350002_P01_FRONT-DECOR-BLOCK-ASSY-DT_CAD (Autodesk Fusion 360 design; units mm, degrees)
part number: 2026-11-01-00-32-53-653
description: FRONT - DECOR SKIN - DT | Tấm ốp alu khối trên | P01
part number: 351201
description: FRONT - DECOR BACK PLATE - DT | Tấm hậu khối trên | P01
part number: 351202
description: FRONT - DOOR CATCH - IN DT | Nam châm hít cửa | P01
part number: 368007
description: FRONT - FRAME-STOP SEAL | Gioăng chặn cửa trên | P01
part number: 368005
description: FRONT - DOOR TOP STOP - DT | Nẹp chặn cửa trên | P01
part number: 351203
description: FRONT - DECOR FRAME - DT | Khung trang trí trên (hàn) | P01
part number: 351204
description: FRONT - DECOR FRAME DT - BACK RING BOTTOM | Mặt trước - khung khối trên - vòng sau - thanh dưới | P01
part number: 352201
description: FRONT - DECOR FRAME DT - BACK RING DR JOINT | Mặt trước - khung khối trên - vòng sau - thanh nối khối phải | P01
part number: 352202
description: FRONT - DECOR FRAME DT - BACK RING TOP | Mặt trước - khung khối trên - vòng sau - thanh trên | P01
part number: 352203
description: FRONT - DECOR FRAME DT - BACK RING SLOPE OVER DL | Mặt trước - khung khối trên - vòng sau - thanh dốc trên khối trái | P01
part number: 352204
description: FRONT - DECOR FRAME DT - BACK RING POST | Mặt trước - khung khối trên - vòng sau - thanh đứng | P01
part number: 352205
description: FRONT - DECOR FRAME DT - FRONT FACET TUBE | Mặt trước - khung khối trên - thanh mặt vát trước | P01
part number: 352206
description: FRONT - DECOR FRAME DT - CATCH AND STOP RAIL | Mặt trước - khung khối trên - thanh gắn chốt hít và nẹp chặn | P01
part number: 352207
description: FRONT - DECOR FRAME DT - CHAMFER TUBE ALONG X | Mặt trước - khung khối trên - thanh vát dọc trục X | P01
part number: 352208
description: FRONT - DECOR FRAME DT - UNDERSIDE CROSS TUBE LEFT | Mặt trước - khung khối trên - thanh ngang mặt dưới - trái | P01
part number: 352209
description: FRONT - DECOR FRAME DT - UNDERSIDE CROSS TUBE OVER THE CATCH | Mặt trước - khung khối trên - thanh ngang mặt dưới - trên chốt hít | P01
part number: 352210
description: FRONT - DECOR FRAME DT - CHAMFER CROSS TUBE - 3 OFF | Mặt trước - khung khối trên - thanh ngang vát (3 thanh) | P01
part number: 352211
Autodesk Fusion 360 part; units mm, degrees
(part 1 of 2)
sketch "PLAN - DT FACETS (SKELETON)" plane through (0, 0, 0) normal (0, 0, 1) x (1, 0, 0) in component "351201 FRONT - DECOR SKIN - DT"
  line L0 (-1250, -647.26) -> (-1250, -670)
  line L1 (-1250, -670) -> (-1154, -753)
  line L2 (-1154, -753) -> (-969, -767)
  line L3 (-969, -767) -> (230, -850)
  line L4 (230, -850) -> (449, -672)
  line L5 (449, -672) -> (449, -647.26)
  line L6 (449, -647.26) -> (-1250, -647.26)
  point P0 (-5000, -5000)
  dimension "d2514" = 5000
  dimension "d2515" = 5000
  dimension "d2516" = 3750
  dimension "d2517" = 3846
  dimension "d2518" = 4031
  dimension "d2519" = 5230
  dimension "d2520" = 5449
  dimension "d2521" = 4330
  dimension "d2522" = 4247
  dimension "d2523" = 4233
  dimension "d2524" = 4150
  dimension "d2526" = 4352.74
  constraint vertical L0
  constraint vertical L5
  constraint horizontal L6
  measures "d2514" horizontal distance of origin P0
  measures "d2515" vertical distance of origin P0
  measures "d2516" horizontal distance of L0.start P0
  measures "d2517" horizontal distance of L1.end P0
  measures "d2518" horizontal distance of L2.end P0
  measures "d2519" horizontal distance of L3.end P0
  measures "d2520" horizontal distance of L4.end P0
  measures "d2521" vertical distance of L0.end P0
  measures "d2522" vertical distance of L1.end P0
  measures "d2523" vertical distance of L2.end P0
  measures "d2524" vertical distance of L3.end P0
  measures "d2526" vertical distance of L5.end P0
extrude "EXTRUDE - DT OUTER SHAPE" add sketch "PLAN - DT FACETS (SKELETON)" along normal blind 280 from surface at 2120 makes body 1 in component "351201 FRONT - DECOR SKIN - DT"
sketch "SLOPE - DT BOTTOM OVER DL" plane through (0, 0, 0) normal (0, 1, 0) x (1, 0, 0) in component "351201 FRONT - DECOR SKIN - DT"
  line L0 (-1250, -2120) -> (-972, -2120)
  line L1 (-972, -2120) -> (-1250, -2397)
  line L2 (-1250, -2397) -> (-1250, -2120)
  point P0 (-5000, 5000)
  dimension "d2530" = 5000
  dimension "d2531" = 5000
  dimension "d2532" = 4028
  dimension "d2533" = 3750
  constraint vertical L2
  constraint horizontal L0
  measures "d2530" horizontal distance of origin P0
  measures "d2531" vertical distance of origin P0
  measures "d2532" horizontal distance of L0.end P0
  measures "d2533" horizontal distance of L1.end P0
extrude "CUT - DT BOTTOM SLOPE" cut sketch "SLOPE - DT BOTTOM OVER DL" along normal blind 205 from surface at -850 bodies 1 in component "351201 FRONT - DECOR SKIN - DT"
sketch "CHAMFER - DT TOP FRONT" plane through (0, 0, 0) normal (1, 0, 0) x (0, 0, -1) in component "351201 FRONT - DECOR SKIN - DT"
  line L0 (-2200, -850) -> (-2400, -672)
  line L1 (-2400, -672) -> (-2400, -850)
  line L2 (-2400, -850) -> (-2200, -850)
  point P0 (5000, -5000)
  dimension "d2539" = 5000
  dimension "d2540" = 5000
  dimension "d2544" = 4150
  constraint vertical L1
  constraint horizontal L2
  measures "d2539" horizontal distance of origin P0
  measures "d2540" vertical distance of origin P0
  measures "d2544" vertical distance of L1.end P0
extrude "CUT - DT TOP CHAMFER" cut sketch "CHAMFER - DT TOP FRONT" along normal blind 2500 from surface at -1250 bodies 1 in component "351201 FRONT - DECOR SKIN - DT"
shell "SHELL - DT SKIN 3 MM (OPEN AT THE BACK AND AT DL, DR)" thickness 3 removed faces 4 at (449, -663.7533, 2213.3333) at (376, -731.3333, 2240) at (-591, -647.26, 2306.6667) at (-1125.3333, -682.5067, 2272.7818) on bodies 1 in component "351201 FRONT - DECOR SKIN - DT"
sketch "SLOT - FIXED GLASS TOP CHANNEL" plane through (0, 0, 0) normal (0, 0, 1) x (1, 0, 0) in component "351201 FRONT - DECOR SKIN - DT"
  line L0 (-65.0827, -707.5) -> (249.8472, -707.5)
  line L1 (249.8472, -707.5) -> (249.8472, -690.5)
  line L2 (249.8472, -690.5) -> (-65.0827, -690.5)
  line L3 (-65.0827, -690.5) -> (-65.0827, -707.5)
  point P0 (-5000, -5000)
  dimension "d2549" = 5000
  dimension "d2550" = 5000
  dimension "d2552" = 4934.9173
  dimension "d2553" = 4292.5
  dimension "d2554" = 4309.5
  constraint vertical L1
  constraint vertical L3
  constraint horizontal L0
  constraint horizontal L2
  measures "d2549" horizontal distance of origin P0
  measures "d2550" vertical distance of origin P0
  measures "d2552" horizontal distance of L2.end P0
  measures "d2553" vertical distance of L0.start P0
  measures "d2554" vertical distance of L1.end P0
extrude "CUT - SKIN SLOT FOR THE TOP CHANNEL" cut sketch "SLOT - FIXED GLASS TOP CHANNEL" along normal blind 5 from surface at 2119 bodies 1 in component "351201 FRONT - DECOR SKIN - DT"
sketch "NOTCH - OVER DR'S LEDGE SPIGOTS" plane through (0, 0, 0) normal (0, 0, 1) x (1, 0, 0) in component "351201 FRONT - DECOR SKIN - DT"
  line L0 (254, -673.88) -> (428.75, -673.88)
  line L1 (428.75, -673.88) -> (428.75, -646.26)
  line L2 (428.75, -646.26) -> (254, -646.26)
  line L3 (254, -646.26) -> (254, -673.88)
  point P0 (-5000, -5000)
  dimension "d2558" = 5000
  dimension "d2559" = 5000
  dimension "d2560" = 5428.75
  dimension "d2561" = 5254
  dimension "d2563" = 4353.74
  constraint vertical L1
  constraint vertical L3
  constraint horizontal L0
  constraint horizontal L2
  measures "d2558" horizontal distance of origin P0
  measures "d2559" vertical distance of origin P0
  measures "d2560" horizontal distance of L0.end P0
  measures "d2561" horizontal distance of L2.end P0
  measures "d2563" vertical distance of L1.end P0
extrude "CUT - UNDERSIDE NOTCH" cut sketch "NOTCH - OVER DR'S LEDGE SPIGOTS" along normal blind 5 from surface at 2119 bodies 1 in component "351201 FRONT - DECOR SKIN - DT"
sketch "OUTLINE - DT BACK PLATE" plane through (0, 0, 0) normal (0, 1, 0) x (1, 0, 0) in component "351202 FRONT - DECOR BACK PLATE - DT"
  line L0 (-970.7605, -2123) -> (449, -2123)
  line L1 (449, -2123) -> (449, -2397)
  line L2 (449, -2397) -> (-1245.7497, -2397)
  line L3 (-1245.7497, -2397) -> (-970.7605, -2123)
  point P0 (-5000, 5000)
  dimension "d2567" = 5000
  dimension "d2568" = 5000
  dimension "d2569" = 4029.2395
  dimension "d2570" = 5449
  dimension "d2571" = 3754.2503
  constraint vertical L1
  constraint horizontal L0
  constraint horizontal L2
  measures "d2567" horizontal distance of origin P0
  measures "d2568" vertical distance of origin P0
  measures "d2569" horizontal distance of L0.start P0
  measures "d2570" horizontal distance of L0.end P0
  measures "d2571" horizontal distance of L2.end P0
extrude "EXTRUDE - DT BACK PLATE" add sketch "OUTLINE - DT BACK PLATE" along normal blind 2 from surface at -649.26 separate body makes body 2 in component "351202 FRONT - DECOR BACK PLATE - DT"
sketch "HOLES - J-FRONT-03 RIVNUTS (4)" plane through (0, 0, 0) normal (0, 1, 0) x (1, 0, 0) in component "351202 FRONT - DECOR BACK PLATE - DT"
  circle A0 centre (-981.74, -2374) radius 4.765
  circle A1 centre (-578.16, -2374) radius 4.765
  circle A2 centre (-174.58, -2374) radius 4.765
  circle A3 centre (229, -2374) radius 4.765
  point P0 (-5000, 5000)
  dimension "d2577" = 5000
  dimension "d2578" = 5000
  dimension "d2579" = 4018.26
  dimension "d2580" = 7374
  dimension "d2581" = 9.53
  dimension "d2582" = 4421.84
  dimension "d2583" = 7374
  dimension "d2584" = 9.53
  dimension "d2585" = 4825.42
  dimension "d2586" = 7374
  dimension "d2587" = 9.53
  dimension "d2588" = 5229
  dimension "d2589" = 7374
  dimension "d2590" = 9.53
  measures "d2577" horizontal distance of origin P0
  measures "d2578" vertical distance of origin P0
  measures "d2579" horizontal distance of P0 A0.centre
  measures "d2580" vertical distance of P0 A0.centre
  measures "d2581" diameter of A0
  measures "d2582" horizontal distance of P0 A1.centre
  measures "d2583" vertical distance of P0 A1.centre
  measures "d2584" diameter of A1
  measures "d2585" horizontal distance of P0 A2.centre
  measures "d2586" vertical distance of P0 A2.centre
  measures "d2587" diameter of A2
  measures "d2588" horizontal distance of P0 A3.centre
  measures "d2589" vertical distance of P0 A3.centre
  measures "d2590" diameter of A3
extrude "CUT - J-FRONT-03 RIVNUT HOLES" cut sketch "HOLES - J-FRONT-03 RIVNUTS (4)" along normal blind 4 from surface at -650.26 bodies 2 in component "351202 FRONT - DECOR BACK PLATE - DT"
sketch "PLAN - CATCH" plane through (0, 0, 0) normal (0, 0, 1) x (1, 0, 0) in component "368007 FRONT - DOOR CATCH - IN DT"
  line L0 (-154.7195, -691.95) -> (-92.7195, -691.95)
  line L1 (-92.7195, -691.95) -> (-92.7195, -671.95)
  line L2 (-92.7195, -671.95) -> (-154.7195, -671.95)
  line L3 (-154.7195, -671.95) -> (-154.7195, -691.95)
  point P0 (-5000, -5000)
  dimension "d2594" = 5000
  dimension "d2595" = 5000
  dimension "d2596" = 4907.2805
  dimension "d2597" = 4845.2805
  dimension "d2598" = 4308.05
  dimension "d2599" = 4328.05
  constraint vertical L1
  constraint vertical L3
  constraint horizontal L0
  constraint horizontal L2
  measures "d2594" horizontal distance of origin P0
  measures "d2595" vertical distance of origin P0
  measures "d2596" horizontal distance of L0.end P0
  measures "d2597" horizontal distance of L2.end P0
  measures "d2598" vertical distance of L0.start P0
  measures "d2599" vertical distance of L1.end P0
extrude "EXTRUDE - CATCH" add sketch "PLAN - CATCH" along normal blind 26 from surface at 2094 separate body makes body 3 in component "368007 FRONT - DOOR CATCH - IN DT"
sketch "PLAN - PS" plane through (0, 0, 0) normal (0, 0, 1) x (1, 0, 0) in component "368005 FRONT - FRAME-STOP SEAL"
  line L0 (-961, -694.62) -> (-164.7195, -694.62)
  line L1 (-164.7195, -694.62) -> (-164.7195, -690.62)
  line L2 (-164.7195, -690.62) -> (-961, -690.62)
  line L3 (-961, -690.62) -> (-961, -694.62)
  point P0 (-5000, -5000)
  dimension "d2603" = 5000
  dimension "d2604" = 5000
  dimension "d2605" = 4835.2805
  dimension "d2606" = 4039
  dimension "d2607" = 4305.38
  dimension "d2608" = 4309.38
  constraint vertical L1
  constraint vertical L3
  constraint horizontal L0
  constraint horizontal L2
  measures "d2603" horizontal distance of origin P0
  measures "d2604" vertical distance of origin P0
  measures "d2605" horizontal distance of L0.end P0
  measures "d2606" horizontal distance of L2.end P0
  measures "d2607" vertical distance of L0.start P0
  measures "d2608" vertical distance of L1.end P0
extrude "EXTRUDE - PS" add sketch "PLAN - PS" along normal blind 15 from surface at 2105 separate body makes body 4 in component "368005 FRONT - FRAME-STOP SEAL"
sketch "SECTION - DOOR TOP STOP (ANGLE)" plane through (0, 0, 0) normal (1, 0, 0) x (0, 0, -1) in component "351203 FRONT - DOOR TOP STOP - DT"
  line L0 (-2100, -690.62) -> (-2100, -688.62)
  line L1 (-2100, -688.62) -> (-2118, -688.62)
  line L2 (-2118, -688.62) -> (-2118, -670.62)
  line L3 (-2118, -670.62) -> (-2120, -670.62)
  line L4 (-2120, -670.62) -> (-2120, -690.62)
  line L5 (-2120, -690.62) -> (-2100, -690.62)
  point P0 (5000, -5000)
  dimension "d2612" = 5000
  dimension "d2613" = 5000
  dimension "d2617" = 4311.38
  dimension "d2618" = 4329.38
  dimension "d2619" = 4309.38
  constraint vertical L0
  constraint vertical L2
  constraint vertical L4
  constraint horizontal L1
  constraint horizontal L3
  constraint horizontal L5
  measures "d2612" horizontal distance of origin P0
  measures "d2613" vertical distance of origin P0
  measures "d2617" vertical distance of L0.end P0
  measures "d2618" vertical distance of L2.end P0
  measures "d2619" vertical distance of L4.end P0
extrude "EXTRUDE - DOOR TOP STOP" add sketch "SECTION - DOOR TOP STOP (ANGLE)" along normal blind 796.2805 from surface at -961 separate body makes body 5 in component "351203 FRONT - DOOR TOP STOP - DT"
sketch "HOLES - TOP STOP SCREWS (5)" plane through (0, 0, 0) normal (0, 0, 1) x (1, 0, 0) in component "351203 FRONT - DOOR TOP STOP - DT"
  circle A0 centre (-911, -679.62) radius 2.15
  circle A1 centre (-736.9299, -679.62) radius 2.15
  circle A2 centre (-562.8598, -679.62) radius 2.15
  circle A3 centre (-388.7897, -679.62) radius 2.15
  circle A4 centre (-214.7195, -679.62) radius 2.15
  point P0 (-5000, -5000)
  dimension "d2623" = 5000
  dimension "d2624" = 5000
  dimension "d2625" = 4089
  dimension "d2626" = 4320.38
  dimension "d2627" = 4.3
  dimension "d2628" = 4263.0701
  dimension "d2629" = 4320.38
  dimension "d2630" = 4.3
  dimension "d2631" = 4437.1402
  dimension "d2632" = 4320.38
  dimension "d2633" = 4.3
  dimension "d2634" = 4611.2103
  dimension "d2635" = 4320.38
  dimension "d2636" = 4.3
  dimension "d2637" = 4785.2805
  dimension "d2638" = 4320.38
  dimension "d2639" = 4.3
  measures "d2623" horizontal distance of origin P0
  measures "d2624" vertical distance of origin P0
  measures "d2625" horizontal distance of P0 A0.centre
  measures "d2626" vertical distance of P0 A0.centre
  measures "d2627" diameter of A0
  measures "d2628" horizontal distance of P0 A1.centre
  measures "d2629" vertical distance of P0 A1.centre
  measures "d2630" diameter of A1
  measures "d2631" horizontal distance of P0 A2.centre
  measures "d2632" vertical distance of P0 A2.centre
  measures "d2633" diameter of A2
  measures "d2634" horizontal distance of P0 A3.centre
  measures "d2635" vertical distance of P0 A3.centre
  measures "d2636" diameter of A3
  measures "d2637" horizontal distance of P0 A4.centre
  measures "d2638" vertical distance of P0 A4.centre
  measures "d2639" diameter of A4
extrude "CUT - TOP STOP SCREW HOLES" cut sketch "HOLES - TOP STOP SCREWS (5)" along normal blind 4 from surface at 2117 bodies 5 in component "351203 FRONT - DOOR TOP STOP - DT"
sketch "TUBE B01 - BACK RING BOTTOM" plane through (0, 0, 0) normal (0, 1, 0) x (1, 0, 0) in component "352201 FRONT - DECOR FRAME DT - BACK RING BOTTOM"
  line L0 (-973.7714, -2126) -> (449, -2126)
  line L1 (449, -2126) -> (429, -2146)
  line L2 (429, -2146) -> (-965.5082, -2146)
  line L3 (-965.5082, -2146) -> (-973.7714, -2126)
  point P0 (-5000, 5000)
  dimension "d2643" = 5000
  dimension "d2644" = 5000
  dimension "d2645" = 4026.2286
  dimension "d2646" = 5449
  dimension "d2647" = 5429
  dimension "d2648" = 4034.4918
  dimension "d2649" = 7126
  constraint horizontal L0
  constraint horizontal L2
  measures "d2643" horizontal distance of origin P0
  measures "d2644" vertical distance of origin P0
  measures "d2645" horizontal distance of L0.start P0
  measures "d2646" horizontal distance of L0.end P0
  measures "d2647" horizontal distance of L1.end P0
  measures "d2648" horizontal distance of L2.end P0
  measures "d2649" vertical distance of L0.start P0
extrude "EXTRUDE - TUBE B01" add sketch "TUBE B01 - BACK RING BOTTOM" along normal blind 20 from surface at -669.26 separate body makes body 6 in component "352201 FRONT - DECOR FRAME DT - BACK RING BOTTOM"
shell "SHELL - TUBE B01 (ENDS OPEN)" thickness 1.5 removed faces 2 at (-968.2626, -662.5933, 2139.3333) at (442.3333, -662.5933, 2132.6667) on bodies 6 in component "352201 FRONT - DECOR FRAME DT - BACK RING BOTTOM"
sketch "TUBE B02 - BACK RING DR JOINT" plane through (0, 0, 0) normal (0, 1, 0) x (1, 0, 0) in component "352202 FRONT - DECOR FRAME DT - BACK RING DR JOINT"
  line L0 (449, -2126) -> (449, -2394)
  line L1 (449, -2394) -> (429, -2354)
  line L2 (429, -2354) -> (429, -2146)
  line L3 (429, -2146) -> (449, -2126)
  point P0 (-5000, 5000)
  dimension "d2655" = 5000
  dimension "d2656" = 5000
  dimension "d2657" = 5449
  dimension "d2658" = 5429
  constraint vertical L0
  constraint vertical L2
  measures "d2655" horizontal distance of origin P0
  measures "d2656" vertical distance of origin P0
  measures "d2657" horizontal distance of L0.start P0
  measures "d2658" horizontal distance of L1.end P0
extrude "EXTRUDE - TUBE B02" add sketch "TUBE B02 - BACK RING DR JOINT" along normal blind 20 from surface at -669.26 separate body makes body 7 in component "352202 FRONT - DECOR FRAME DT - BACK RING DR JOINT"
shell "SHELL - TUBE B02 (ENDS OPEN)" thickness 1.5 removed faces 2 at (435.6667, -655.9267, 2139.3333) at (442.3333, -662.5933, 2380.6667) on bodies 7 in component "352202 FRONT - DECOR FRAME DT - BACK RING DR JOINT"
sketch "TUBE B03 - BACK RING TOP" plane through (0, 0, 0) normal (0, 1, 0) x (1, 0, 0) in component "352203 FRONT - DECOR FRAME DT - BACK RING TOP"
  line L0 (449, -2394) -> (-1242.7389, -2394)
  line L1 (-1242.7389, -2394) -> (-1174.2591, -2354)
  line L2 (-1174.2591, -2354) -> (429, -2354)
  line L3 (429, -2354) -> (449, -2394)
  point P0 (-5000, 5000)
  dimension "d2667" = 5000
  dimension "d2668" = 5000
  dimension "d2669" = 5449
  dimension "d2670" = 3757.2611
  dimension "d2671" = 3825.7409
  dimension "d2672" = 5429
  dimension "d2674" = 7354
  constraint horizontal L0
  constraint horizontal L2
  measures "d2667" horizontal distance of origin P0
  measures "d2668" vertical distance of origin P0
  measures "d2669" horizontal distance of L0.start P0
  measures "d2670" horizontal distance of L0.end P0
  measures "d2671" horizontal distance of L1.end P0
  measures "d2672" horizontal distance of L2.end P0
  measures "d2674" vertical distance of L1.end P0
extrude "EXTRUDE - TUBE B03" add sketch "TUBE B03 - BACK RING TOP" along normal blind 20 from surface at -669.26 separate body makes body 8 in component "352203 FRONT - DECOR FRAME DT - BACK RING TOP"
shell "SHELL - TUBE B03 (ENDS OPEN)" thickness 1.5 removed faces 2 at (435.6667, -655.9267, 2367.3333) at (-1219.9123, -662.5933, 2380.6667) on bodies 8 in component "352203 FRONT - DECOR FRAME DT - BACK RING TOP"
sketch "TUBE B04 - BACK RING SLOPE OVER DL" plane through (0, 0, 0) normal (0, 1, 0) x (1, 0, 0) in component "352204 FRONT - DECOR FRAME DT - BACK RING SLOPE OVER DL"
  line L0 (-1242.7389, -2394) -> (-973.7714, -2126)
  line L1 (-973.7714, -2126) -> (-965.5082, -2146)
  line L2 (-965.5082, -2146) -> (-1174.2591, -2354)
  line L3 (-1174.2591, -2354) -> (-1242.7389, -2394)
  point P0 (-5000, 5000)
  dimension "d2679" = 5000
  dimension "d2680" = 5000
  dimension "d2681" = 3757.2611
  dimension "d2682" = 4026.2286
  dimension "d2683" = 4034.4918
  dimension "d2684" = 3825.7409
  dimension "d2685" = 7394
  dimension "d2686" = 7126
  dimension "d2687" = 7146
  dimension "d2688" = 7354
  measures "d2679" horizontal distance of origin P0
  measures "d2680" vertical distance of origin P0
  measures "d2681" horizontal distance of L0.start P0
  measures "d2682" horizontal distance of L0.end P0
  measures "d2683" horizontal distance of L1.end P0
  measures "d2684" horizontal distance of L2.end P0
  measures "d2685" vertical distance of L0.start P0
  measures "d2686" vertical distance of L0.end P0
  measures "d2687" vertical distance of L1.end P0
  measures "d2688" vertical distance of L2.end P0
extrude "EXTRUDE - TUBE B04" add sketch "TUBE B04 - BACK RING SLOPE OVER DL" along normal blind 20 from surface at -669.26 separate body makes body 9 in component "352204 FRONT - DECOR FRAME DT - BACK RING SLOPE OVER DL"
shell "SHELL - TUBE B04 (ENDS OPEN)" thickness 1.5 removed faces 2 at (-1197.0857, -655.9267, 2367.3333) at (-971.017, -662.5933, 2132.6667) on bodies 9 in component "352204 FRONT - DECOR FRAME DT - BACK RING SLOPE OVER DL"
sketch "TUBE B05 - BACK RING POST" plane through (0, 0, 0) normal (0, 1, 0) x (1, 0, 0) in component "352205 FRONT - DECOR FRAME DT - BACK RING POST"
  line L0 (-271.5, -2146) -> (-251.5, -2146)
  line L1 (-251.5, -2146) -> (-251.5, -2354)
  line L2 (-251.5, -2354) -> (-271.5, -2354)
  line L3 (-271.5, -2354) -> (-271.5, -2146)
  point P0 (-5000, 5000)
  dimension "d2693" = 5000
  dimension "d2694" = 5000
  dimension "d2695" = 4748.5
  dimension "d2696" = 4728.5
  constraint vertical L1
  constraint vertical L3
  constraint horizontal L0
  constraint horizontal L2
  measures "d2693" horizontal distance of origin P0
  measures "d2694" vertical distance of origin P0
  measures "d2695" horizontal distance of L0.end P0
  measures "d2696" horizontal distance of L2.end P0
extrude "EXTRUDE - TUBE B05" add sketch "TUBE B05 - BACK RING POST" along normal blind 20 from surface at -669.26 separate body makes body 10 in component "352205 FRONT - DECOR FRAME DT - BACK RING POST"
shell "SHELL - TUBE B05 (ENDS OPEN)" thickness 1.5 removed faces 2 at (-264.8333, -662.5933, 2146) at (-258.1667, -662.5933, 2354) on bodies 10 in component "352205 FRONT - DECOR FRAME DT - BACK RING POST"
sketch "TUBE F01 - FRONT FACET TUBE" plane through (0, 0, 0) normal (0, 0, 1) x (1, 0, 0) in component "352206 FRONT - DECOR FRAME DT - FRONT FACET TUBE"
  line L0 (-969, -760.9856) -> (236.8189, -844.4577)
  line L1 (236.8189, -844.4577) -> (259.5487, -825.9833)
  line L2 (259.5487, -825.9833) -> (-969, -740.9378)
  line L3 (-969, -740.9378) -> (-969, -760.9856)
  point P0 (-5000, -5000)
  dimension "d2703" = 5000
  dimension "d2704" = 5000
  dimension "d2705" = 5236.8189
  dimension "d2706" = 5259.5487
  dimension "d2707" = 4031
  dimension "d2708" = 4239.0144
  dimension "d2709" = 4155.5423
  dimension "d2710" = 4174.0167
  dimension "d2711" = 4259.0622
  constraint vertical L3
  measures "d2703" horizontal distance of origin P0
  measures "d2704" vertical distance of origin P0
  measures "d2705" horizontal distance of L0.end P0
  measures "d2706" horizontal distance of L1.end P0
  measures "d2707" horizontal distance of L2.end P0
  measures "d2708" vertical distance of L0.start P0
  measures "d2709" vertical distance of L0.end P0
  measures "d2710" vertical distance of L1.end P0
  measures "d2711" vertical distance of L2.end P0
extrude "EXTRUDE - TUBE F01" add sketch "TUBE F01 - FRONT FACET TUBE" along normal blind 20 from surface at 2126 separate body makes body 11 in component "352206 FRONT - DECOR FRAME DT - FRONT FACET TUBE"
shell "SHELL - TUBE F01 (ENDS OPEN)" thickness 1.5 removed faces 2 at (244.3955, -838.2995, 2139.3333) at (-969, -747.6204, 2132.6667) on bodies 11 in component "352206 FRONT - DECOR FRAME DT - FRONT FACET TUBE"
sketch "TUBE F02 - CATCH AND STOP RAIL" plane through (0, 0, 0) normal (0, 0, 1) x (1, 0, 0) in component "352207 FRONT - DECOR FRAME DT - CATCH AND STOP RAIL"
  line L0 (-973.7714, -689.26) -> (427.7644, -689.26)
  line L1 (427.7644, -689.26) -> (449, -672)
  line L2 (449, -672) -> (449, -669.26)
  line L3 (449, -669.26) -> (-973.7714, -669.26)
  line L4 (-973.7714, -669.26) -> (-973.7714, -689.26)
  point P0 (-5000, -5000)
  dimension "d2716" = 5000
  dimension "d2717" = 5000
  dimension "d2718" = 5427.7644
  dimension "d2719" = 5449
  dimension "d2720" = 4026.2286
  dimension "d2721" = 4310.74
  dimension "d2722" = 4328
  dimension "d2723" = 4330.74
  constraint vertical L2
  constraint vertical L4
  constraint horizontal L0
  constraint horizontal L3
  measures "d2716" horizontal distance of origin P0
  measures "d2717" vertical distance of origin P0
  measures "d2718" horizontal distance of L0.end P0
  measures "d2719" horizontal distance of L1.end P0
  measures "d2720" horizontal distance of L3.end P0
  measures "d2721" vertical distance of L0.start P0
  measures "d2722" vertical distance of L1.end P0
  measures "d2723" vertical distance of L2.end P0
extrude "EXTRUDE - TUBE F02" add sketch "TUBE F02 - CATCH AND STOP RAIL" along normal blind 20 from surface at 2126 separate body makes body 12 in component "352207 FRONT - DECOR FRAME DT - CATCH AND STOP RAIL"
shell "SHELL - TUBE F02 (ENDS OPEN)" thickness 1.5 removed faces 3 at (449, -671.0867, 2132.6667) at (434.8429, -683.5067, 2132.6667) at (-973.7714, -675.9267, 2132.6667) on bodies 12 in component "352207 FRONT - DECOR FRAME DT - CATCH AND STOP RAIL"
sketch "TUBE F03 - CHAMFER TUBE ALONG X" plane through (0, 0, 0) normal (1, 0, 0) x (0, 0, -1) in component "352208 FRONT - DECOR FRAME DT - CHAMFER TUBE ALONG X"
  line L0 (-2290.9912, -760.9856) -> (-2305.9312, -747.6891)
  line L1 (-2305.9312, -747.6891) -> (-2292.6346, -732.7492)
  line L2 (-2292.6346, -732.7492) -> (-2277.6947, -746.0457)
  line L3 (-2277.6947, -746.0457) -> (-2290.9912, -760.9856)
  point P0 (5000, -5000)
  dimension "d2728" = 5000
  dimension "d2729" = 5000
  dimension "d2730" = 7290.9912
  dimension "d2731" = 7305.9312
  dimension "d2732" = 7292.6346
  dimension "d2733" = 7277.6947
  dimension "d2734" = 4239.0144
  dimension "d2735" = 4252.3109
  dimension "d2736" = 4267.2508
  dimension "d2737" = 4253.9543
  measures "d2728" horizontal distance of origin P0
  measures "d2729" vertical distance of origin P0
  measures "d2730" horizontal distance of L0.start P0
  measures "d2731" horizontal distance of L0.end P0
  measures "d2732" horizontal distance of L1.end P0
  measures "d2733" horizontal distance of L2.end P0
  measures "d2734" vertical distance of L0.start P0
  measures "d2735" vertical distance of L0.end P0
  measures "d2736" vertical distance of L1.end P0
  measures "d2737" vertical distance of L2.end P0
extrude "EXTRUDE - TUBE F03" add sketch "TUBE F03 - CHAMFER TUBE ALONG X" along normal blind 1308.5177 from surface at -969 separate body makes body 13 in component "352208 FRONT - DECOR FRAME DT - CHAMFER TUBE ALONG X"
shell "SHELL - TUBE F03 (ENDS OPEN)" thickness 1.5 removed faces 2 at (339.5177, -751.5735, 2291.539) at (-969, -751.5735, 2291.539) on bodies 13 in component "352208 FRONT - DECOR FRAME DT - CHAMFER TUBE ALONG X"
sketch "TUBE R01 - UNDERSIDE CROSS TUBE LEFT" plane through (0, 0, 0) normal (0, 0, 1) x (1, 0, 0) in component "352209 FRONT - DECOR FRAME DT - UNDERSIDE CROSS TUBE LEFT"
  line L0 (-689, -760.3206) -> (-669, -761.7051)
  line L1 (-669, -761.7051) -> (-669, -689.26)
  line L2 (-669, -689.26) -> (-689, -689.26)
  line L3 (-689, -689.26) -> (-689, -760.3206)
  point P0 (-5000, -5000)
  dimension "d2742" = 5000
  dimension "d2743" = 5000
  dimension "d2744" = 4331
  dimension "d2745" = 4311
  dimension "d2746" = 4239.6794
  dimension "d2747" = 4238.2949
  dimension "d2748" = 4310.74
  constraint vertical L1
  constraint vertical L3
  constraint horizontal L2
  measures "d2742" horizontal distance of origin P0
  measures "d2743" vertical distance of origin P0
  measures "d2744" horizontal distance of L0.end P0
  measures "d2745" horizontal distance of L2.end P0
  measures "d2746" vertical distance of L0.start P0
  measures "d2747" vertical distance of L0.end P0
  measures "d2748" vertical distance of L1.end P0
extrude "EXTRUDE - TUBE R01" add sketch "TUBE R01 - UNDERSIDE CROSS TUBE LEFT" along normal blind 20 from surface at 2126 separate body makes body 14 in component "352209 FRONT - DECOR FRAME DT - UNDERSIDE CROSS TUBE LEFT"
shell "SHELL - TUBE R01 (ENDS OPEN)" thickness 1.5 removed faces 2 at (-675.6667, -689.26, 2132.6667) at (-682.3333, -760.7821, 2132.6667) on bodies 14 in component "352209 FRONT - DECOR FRAME DT - UNDERSIDE CROSS TUBE LEFT"
sketch "TUBE R02 - UNDERSIDE CROSS TUBE OVER THE CATCH" plane through (0, 0, 0) normal (0, 0, 1) x (1, 0, 0) in component "352210 FRONT - DECOR FRAME DT - UNDERSIDE CROSS TUBE OVER THE CATCH"
  line L0 (-133.7195, -798.7595) -> (-113.7195, -800.144)
  line L1 (-113.7195, -800.144) -> (-113.7195, -689.26)
  line L2 (-113.7195, -689.26) -> (-133.7195, -689.26)
  line L3 (-133.7195, -689.26) -> (-133.7195, -798.7595)
  point P0 (-5000, -5000)
  dimension "d2753" = 5000
  dimension "d2754" = 5000
  dimension "d2755" = 4886.2805
  dimension "d2756" = 4866.2805
  dimension "d2757" = 4201.2405
  dimension "d2758" = 4199.856
  dimension "d2759" = 4310.74
  constraint vertical L1
  constraint vertical L3
  constraint horizontal L2
  measures "d2753" horizontal distance of origin P0
  measures "d2754" vertical distance of origin P0
  measures "d2755" horizontal distance of L0.end P0
  measures "d2756" horizontal distance of L2.end P0
  measures "d2757" vertical distance of L0.start P0
  measures "d2758" vertical distance of L0.end P0
  measures "d2759" vertical distance of L1.end P0
extrude "EXTRUDE - TUBE R02" add sketch "TUBE R02 - UNDERSIDE CROSS TUBE OVER THE CATCH" along normal blind 20 from surface at 2126 separate body makes body 15 in component "352210 FRONT - DECOR FRAME DT - UNDERSIDE CROSS TUBE OVER THE CATCH"
shell "SHELL - TUBE R02 (ENDS OPEN)" thickness 1.5 removed faces 2 at (-120.3862, -689.26, 2132.6667) at (-127.0529, -799.221, 2132.6667) on bodies 15 in component "352210 FRONT - DECOR FRAME DT - UNDERSIDE CROSS TUBE OVER THE CATCH"
sketch "TUBE C01 - CHAMFER CROSS TUBE LEFT" plane through (0, 0, 0) normal (1, 0, 0) x (0, 0, -1) in component "352211 FRONT - DECOR FRAME DT - CHAMFER CROSS TUBE - 3 OFF"
  line L0 (-2305.9312, -747.6891) -> (-2394, -669.3078)
  line L1 (-2394, -669.3078) -> (-2363.9708, -669.26)
  line L2 (-2363.9708, -669.26) -> (-2292.6346, -732.7492)
  line L3 (-2292.6346, -732.7492) -> (-2305.9312, -747.6891)
  point P0 (5000, -5000)
  dimension "d2764" = 5000
  dimension "d2765" = 5000
  dimension "d2766" = 7305.9312
  dimension "d2768" = 7363.9708
  dimension "d2769" = 7292.6346
  dimension "d2770" = 4252.3109
  dimension "d2771" = 4330.6922
  dimension "d2772" = 4330.74
  dimension "d2773" = 4267.2508
  measures "d2764" horizontal distance of origin P0
  measures "d2765" vertical distance of origin P0
  measures "d2766" horizontal distance of L0.start P0
  measures "d2768" horizontal distance of L1.end P0
  measures "d2769" horizontal distance of L2.end P0
  measures "d2770" vertical distance of L0.start P0
  measures "d2771" vertical distance of L0.end P0
  measures "d2772" vertical distance of L1.end P0
  measures "d2773" vertical distance of L2.end P0
extrude "EXTRUDE - TUBE C01" add sketch "TUBE C01 - CHAMFER CROSS TUBE LEFT" along normal blind 20 from surface at -689 separate body makes body 16 in component "352211 FRONT - DECOR FRAME DT - CHAMFER CROSS TUBE - 3 OFF"
shell "SHELL - TUBE C01 (ENDS OPEN)" thickness 1.5 removed faces 2 at (-675.6667, -737.7291, 2297.0668) at (-682.3333, -669.2919, 2383.9903) on bodies 16 in component "352211 FRONT - DECOR FRAME DT - CHAMFER CROSS TUBE - 3 OFF"
ref_plane "WorkPlane1" through (555.2805, 0, 0) normal (1, 0, 0) x (0, 1, 0) in component "351204 FRONT - DECOR FRAME - DT"
ref_plane "WorkPlane2" through (988.5177, 0, 0) normal (1, 0, 0) x (0, 1, 0) in component "351204 FRONT - DECOR FRAME - DT"
sketch "HOLES - J-FRONT-03 RIVNUT TAILS (4)" plane through (0, 0, 0) normal (0, 1, 0) x (1, 0, 0) in component "352203 FRONT - DECOR FRAME DT - BACK RING TOP"
  circle A0 centre (-981.74, -2374) radius 7
  circle A1 centre (-578.16, -2374) radius 7
  circle A2 centre (-174.58, -2374) radius 7
  circle A3 centre (229, -2374) radius 7
  point P0 (-5000, 5000)
  dimension "d2790" = 5000
  dimension "d2791" = 5000
  dimension "d2792" = 4018.26
  dimension "d2793" = 7374
  dimension "d2794" = 14
  dimension "d2795" = 4421.84
  dimension "d2796" = 7374
  dimension "d2797" = 14
  dimension "d2798" = 4825.42
  dimension "d2799" = 7374
  dimension "d2800" = 14
  dimension "d2801" = 5229
  dimension "d2802" = 7374
  dimension "d2803" = 14
  measures "d2790" horizontal distance of origin P0
  measures "d2791" vertical distance of origin P0
  measures "d2792" horizontal distance of P0 A0.centre
  measures "d2793" vertical distance of P0 A0.centre
  measures "d2794" diameter of A0
  measures "d2795" horizontal distance of P0 A1.centre
  measures "d2796" vertical distance of P0 A1.centre
  measures "d2797" diameter of A1
  measures "d2798" horizontal distance of P0 A2.centre
  measures "d2799" vertical distance of P0 A2.centre
  measures "d2800" diameter of A2
  measures "d2801" horizontal distance of P0 A3.centre
  measures "d2802" vertical distance of P0 A3.centre
  measures "d2803" diameter of A3
extrude "CUT - J-FRONT-03 RIVNUT TAILS" cut sketch "HOLES - J-FRONT-03 RIVNUT TAILS (4)" along normal blind 3 from surface at -651.76 bodies 8 in component "352203 FRONT - DECOR FRAME DT - BACK RING TOP"
sketch "HOLES - SPIGOT ROUND AND SLOT ENDS" plane through (0, 0, 0) normal (0, 0, 1) x (1, 0, 0) in component "352201 FRONT - DECOR FRAME DT - BACK RING BOTTOM"
  circle A0 centre (270, -657.88) radius 4.25
  circle A1 centre (407.25, -657.88) radius 4.25
  circle A2 centre (412.75, -657.88) radius 4.25
  point P0 (-5000, -5000)
  dimension "d2807" = 5000
  dimension "d2808" = 5000
  dimension "d2809" = 5270
  dimension "d2811" = 8.5
  dimension "d2812" = 5407.25
  dimension "d2814" = 8.5
  dimension "d2815" = 5412.75
  dimension "d2817" = 8.5
  measures "d2807" horizontal distance of origin P0
  measures "d2808" vertical distance of origin P0
  measures "d2809" horizontal distance of P0 A0.centre
  measures "d2811" diameter of A0
  measures "d2812" horizontal distance of P0 A1.centre
  measures "d2814" diameter of A1
  measures "d2815" horizontal distance of P0 A2.centre
  measures "d2817" diameter of A2
extrude "CUT - SPIGOT HOLE AND SLOT ENDS" cut sketch "HOLES - SPIGOT ROUND AND SLOT ENDS" along normal blind 3 from surface at 2125 bodies 6 in component "352201 FRONT - DECOR FRAME DT - BACK RING BOTTOM"
sketch "SLOT - SPIGOT (MIDDLE)" plane through (0, 0, 0) normal (0, 0, 1) x (1, 0, 0) in component "352201 FRONT - DECOR FRAME DT - BACK RING BOTTOM"
  line L0 (407.25, -662.13) -> (412.75, -662.13)
  line L1 (412.75, -662.13) -> (412.75, -653.63)
  line L2 (412.75, -653.63) -> (407.25, -653.63)
  line L3 (407.25, -653.63) -> (407.25, -662.13)
  point P0 (-5000, -5000)
  dimension "d2821" = 5000
  dimension "d2822" = 5000
  dimension "d2823" = 5412.75
  dimension "d2824" = 5407.25
  dimension "d2825" = 4337.87
  dimension "d2826" = 4346.37
  constraint vertical L1
  constraint vertical L3
  constraint horizontal L0
  constraint horizontal L2
  measures "d2821" horizontal distance of origin P0
  measures "d2822" vertical distance of origin P0
  measures "d2823" horizontal distance of L0.end P0
  measures "d2824" horizontal distance of L2.end P0
  measures "d2825" vertical distance of L0.start P0
  measures "d2826" vertical distance of L1.end P0
extrude "CUT - SPIGOT SLOT MIDDLE" cut sketch "SLOT - SPIGOT (MIDDLE)" along normal blind 3 from surface at 2125 bodies 6 in component "352201 FRONT - DECOR FRAME DT - BACK RING BOTTOM"
component "351201 FRONT - DECOR SKIN - DT" placed x (1, 0, 0) y (0, 1, 0) z (0, 0, 1) at (0, 0, 0)
component "351202 FRONT - DECOR BACK PLATE - DT" placed x (1, 0, 0) y (0, 1, 0) z (0, 0, 1) at (0, 0, 0)
component "368007 FRONT - DOOR CATCH - IN DT" placed x (1, 0, 0) y (0, 1, 0) z (0, 0, 1) at (0, 0, 0)
component "368005 FRONT - FRAME-STOP SEAL" placed x (1, 0, 0) y (0, 1, 0) z (0, 0, 1) at (0, 0, 0)
component "351203 FRONT - DOOR TOP STOP - DT" placed x (1, 0, 0) y (0, 1, 0) z (0, 0, 1) at (0, 0, 0)
component "351204 FRONT - DECOR FRAME - DT" placed x (1, 0, 0) y (0, 1, 0) z (0, 0, 1) at (0, 0, 0)
component "352201 FRONT - DECOR FRAME DT - BACK RING BOTTOM" placed x (1, 0, 0) y (0, 1, 0) z (0, 0, 1) at (0, 0, 0) in component "351204 FRONT - DECOR FRAME - DT"
component "352202 FRONT - DECOR FRAME DT - BACK RING DR JOINT" placed x (1, 0, 0) y (0, 1, 0) z (0, 0, 1) at (0, 0, 0) in component "351204 FRONT - DECOR FRAME - DT"
component "352203 FRONT - DECOR FRAME DT - BACK RING TOP" placed x (1, 0, 0) y (0, 1, 0) z (0, 0, 1) at (0, 0, 0) in component "351204 FRONT - DECOR FRAME - DT"
component "352204 FRONT - DECOR FRAME DT - BACK RING SLOPE OVER DL" placed x (1, 0, 0) y (0, 1, 0) z (0, 0, 1) at (0, 0, 0) in component "351204 FRONT - DECOR FRAME - DT"
component "352205 FRONT - DECOR FRAME DT - BACK RING POST" placed x (1, 0, 0) y (0, 1, 0) z (0, 0, 1) at (0, 0, 0) in component "351204 FRONT - DECOR FRAME - DT"
component "352206 FRONT - DECOR FRAME DT - FRONT FACET TUBE" placed x (1, 0, 0) y (0, 1, 0) z (0, 0, 1) at (0, 0, 0) in component "351204 FRONT - DECOR FRAME - DT"
component "352207 FRONT - DECOR FRAME DT - CATCH AND STOP RAIL" placed x (1, 0, 0) y (0, 1, 0) z (0, 0, 1) at (0, 0, 0) in component "351204 FRONT - DECOR FRAME - DT"
component "352208 FRONT - DECOR FRAME DT - CHAMFER TUBE ALONG X" placed x (1, 0, 0) y (0, 1, 0) z (0, 0, 1) at (0, 0, 0) in component "351204 FRONT - DECOR FRAME - DT"
component "352209 FRONT - DECOR FRAME DT - UNDERSIDE CROSS TUBE LEFT" placed x (1, 0, 0) y (0, 1, 0) z (0, 0, 1) at (0, 0, 0) in component "351204 FRONT - DECOR FRAME - DT"
component "352210 FRONT - DECOR FRAME DT - UNDERSIDE CROSS TUBE OVER THE CATCH" placed x (1, 0, 0) y (0, 1, 0) z (0, 0, 1) at (0, 0, 0) in component "351204 FRONT - DECOR FRAME - DT"
component "352211 FRONT - DECOR FRAME DT - CHAMFER CROSS TUBE - 3 OFF" placed x (1, 0, 0) y (0, 1, 0) z (0, 0, 1) at (0, 0, 0) in component "351204 FRONT - DECOR FRAME - DT"
component "352211 FRONT - DECOR FRAME DT - CHAMFER CROSS TUBE - 3 OFF" placed x (1, 0, 0) y (0, 1, 0) z (0, 0, 1) at (555.2805, 0, 0) in component "351204 FRONT - DECOR FRAME - DT"
component "352211 FRONT - DECOR FRAME DT - CHAMFER CROSS TUBE - 3 OFF" placed x (1, 0, 0) y (0, 1, 0) z (0, 0, 1) at (988.5177, 0, 0) in component "351204 FRONT - DECOR FRAME - DT"
equation "pod_w = 2500 mm" comment "SKELETON P04 DECIDED: D-01; conventions s4 (X = +-1250)"
equation "pod_d = 1700 mm" comment "SKELETON P04 DECIDED: D-01; conventions s4 (Y = +-850)"
equation "pod_h = 2400 mm" comment "SKELETON P04 DECIDED: D-21 (room floor to roof skin top)"
equation "glide_h = 10 mm" comment "SKELETON P04 ASSUMPTION: layout study inputs.py glide_h"
equation "band_h = 100 mm" comment "SKELETON P04 SOURCE: layout study B1 list B-BAND 100x40; inputs.py base_h"
equation "band_t = 40 mm" comment "SKELETON P04 SOURCE: layout study B1 list B-BAND 100x40"
equation "skin_t = 3 mm" comment "SKELETON P04 DECIDED: ACP skin, walls and ceiling (D-16; PM ruling 2026-10-31 on outer_t)"
equation "bond_t = 3 mm" comment "SKELETON P04 DECIDED: bond line between the ACP and the frame (PM ruling 2026-10-31 on outer_t)"
equation "frame_t = 40 mm" comment "SKELETON P04 DECIDED: aluminium frame tube depth, walls and ceiling (PM ruling 2026-10-31 on outer_t)"
equation "outer_t = skin_t + bond_t + frame_t" comment "SKELETON P04 DECIDED: PM ruling 2026-10-31: ACP 3 + bond line 3 + frame 40, walls and ceiling (was 43)"
equation "cav_gap = 4 mm" comment "SKELETON P04 DECIDED: D-16, D-42: the gap between the outer panel and the lining cassette in the wall and ceiling stack"
equation "cass_t = 34 mm" comment "SKELETON P04 SOURCE: layout study B1 final list L-CASS 34 (tray + 25 gap + felt 9)"
equation "stack_t = outer_t + cav_gap + cass_t" comment "SKELETON P04 CALCULATION: D-16, D-42 stack, walls and ceiling: outer panel + cavity gap + cassette (PM ruling 2026-10-31 on outer_t)"
equation "wall_depth = 1495 mm" comment "SKELETON P04 DECIDED: PM ruling pass C: side walls start at the decor back plate (Y -645), as v1 (1496)"
equation "lin_gap = 4 mm" comment "SKELETON P04 ASSUMPTION: PM ruling pass C: gap above the upper side linings so they stay floating (= the 4 mm stack gap)"
equation "seam_gap = 2.26 mm" comment "SKELETON P04 DECIDED: PM ruling 2026-10-31 (Mechanical Checker F-001, F-005): the Joints Engineer's 2.26 mm at all nine site seam types, set by a metal stop (1.5 stop washer + 0.76 rivnut head; joints register section 2.8)"
equation "mat_t = 3 mm" comment "SKELETON P04 DECIDED: D-72, PM ruling 2026-10-31 (from BASE): the 3 mm floor mat under the floor ply"
equation "floor_t = 9 mm" comment "SKELETON P04 DECIDED: PM ruling 2026-10-31: 9 mm floor panels (was 15, layout study B1 list), on the mat"
equation "thresh_h = 13 mm" comment "SKELETON P04 DECIDED: PM ruling 2026-10-31: 13 mm, a US-accessible threshold (D-18 had 20); the kick strip keeps its kick_gap above it"
equation "thresh_d = 60 mm" comment "SKELETON P04 SOURCE: layout study B1 list B-THRESH 1176 x 60 x 20"
equation "decor_d = 205 mm" comment "SKELETON P04 SOURCE: v1 geometry per the PM ruling on D-39 (as v1; the drawings win): v1 decor-frame drawing frames 191 (left) and 197 (right) deep plus ACP and back plate = the v1 STEP shell, Y -850 to -645 = 205. D-39 and the B1 list say 230-235 (v1 BOM); see BUILD-RECORD-P02"
equation "dl_w = 278 mm" comment "SKELETON P04 SOURCE: B1 list F-DL 278 (v1 BOM DL)"
equation "dr_w = 1016 mm" comment "SKELETON P04 SOURCE: B1 list F-DR 1016 (v1 STEP solid 78)"
equation "dt_w = 1697 mm" comment "SKELETON P04 SOURCE: B1 list F-DT 1697 (v1 BOM DT)"
equation "dt_h = 280 mm" comment "SKELETON P04 SOURCE: B1 list F-DT 280"
equation "door_w = 1176 mm" comment "SKELETON P04 DECIDED: D-46"
equation "door_h = 2011 mm" comment "SKELETON P04 SOURCE: B1 list F-GLASS-DOOR 2011; v1 STEP solid 238"
equation "glass_t = 8.76 mm" comment "SKELETON P04 DECIDED: D-46 (4+4 laminate)"
equation "glass_y = 699 mm" comment "SKELETON P04 SOURCE: v1 STEP solid 238 centre Y = -699 (layout study data)"
equation "kick_d = 20 mm" comment "SKELETON P04 ASSUMPTION: kick strip envelope depth (D-40 gives the height only)"
equation "kick_gap = 7 mm" comment "SKELETON P04 SOURCE: FRONT door unit: 7 mm running gap between the threshold and the kick strip for the drop seal (Mechanical Checker F-002 on P03)"
equation "fr_dz = 17 mm" comment "SKELETON P04 CALCULATION: v1 front top 2417 (v2 frame) - pod_h 2400"
equation "door_xl = 289 mm" comment "SKELETON P04 SOURCE: V1-FRONT-FACETS: door left edge X -961 = -1250 + 289"
equation "door_xbr = 1464 mm" comment "SKELETON P04 SOURCE: V1-FRONT-FACETS: door bottom-right X 214"
equation "door_xtr = 1182 mm" comment "SKELETON P04 SOURCE: V1-FRONT-FACETS: door top-right X -68"
equation "door_zb = 122 mm - fr_dz" comment "SKELETON P04 SOURCE: V1-FRONT-FACETS: door bottom Z 122"
equation "door_zt = 2133 mm - fr_dz" comment "SKELETON P04 SOURCE: V1-FRONT-FACETS: door top Z 2133"
equation "glass_gap = 4 mm" comment "SKELETON P04 DECIDED: PM ruling 2026-10-31 on Mechanical Checker F-014: the fixed glass's free edge runs parallel to the door's slanted edge, 4.0 mm away (FRONT's glass in PR #28 is the reference)"
equation "fix_xbr = 302 mm" comment "SKELETON P04 SOURCE: V1-FRONT-FACETS: fixed glass bottom-right X 948 = 1250 - 302"
equation "fix_xk = 501 mm" comment "SKELETON P04 SOURCE: V1-FRONT-FACETS: fixed glass knee X 749 = 1250 - 501"
equation "fix_zk = 1538 mm - fr_dz" comment "SKELETON P04 SOURCE: V1-FRONT-FACETS: fixed glass knee Z 1538"
equation "fix_xtr = 1480 mm" comment "SKELETON P04 SOURCE: V1-FRONT-FACETS: fixed glass top-right X 230 = -1250 + 1480"
equation "fix_zb = 119 mm - fr_dz" comment "SKELETON P04 SOURCE: V1-FRONT-FACETS: fixed glass bottom Z 119"
equation "fix_zt = 2136 mm - fr_dz" comment "SKELETON P04 SOURCE: V1-FRONT-FACETS: fixed glass top Z 2136"
equation "dt_zb = 2137 mm - fr_dz" comment "SKELETON P04 SOURCE: V1-FRONT-FACETS: DT and DR edge above the glass Z 2137"
equation "ch_zlo = 2217 mm - fr_dz" comment "SKELETON P04 SOURCE: V1-FRONT-FACETS: top chamfer front edge Z 2217 at Y -848"
equation "ch_yb = 672 mm" comment "SKELETON P04 SOURCE: V1-FRONT-FACETS: top chamfer back edge Y -672"
equation "dl_x2 = 92 mm" comment "SKELETON P04 SOURCE: V1-FRONT-FACETS: DL facet knee X -1158 = -1250 + 92"
equation "dl_y2 = 752 mm" comment "SKELETON P04 SOURCE: V1-FRONT-FACETS: DL facet knee Y -752"
equation "dl_x3 = 271 mm" comment "SKELETON P04 SOURCE: V1-FRONT-FACETS: DL front corner X -979"
equation "dl_y3 = 844 mm" comment "SKELETON P04 SOURCE: V1-FRONT-FACETS: DL front corner Y -844"
equation "dl_y1 = 670 mm" comment "SKELETON P04 SOURCE: V1-FRONT-FACETS: DL outer facet start Y -670"
equation "dl_zo = 2414 mm - fr_dz" comment "SKELETON P04 SOURCE: V1-FRONT-FACETS: DL top at the outer corner Z 2414"
equation "dt_x2 = 281 mm" comment "SKELETON P04 SOURCE: V1-FRONT-FACETS: DT lower facet left X -969 = -1250 + 281"
equation "dt_y2 = 767 mm" comment "SKELETON P04 SOURCE: V1-FRONT-FACETS: DT lower facet left Y -767"
equation "dt_y3 = 753 mm" comment "SKELETON P04 SOURCE: V1-FRONT-FACETS: DT lower facet outer Y -753 at X -1154"
equation "dr_xc = 198 mm" comment "SKELETON P04 SOURCE: V1-FRONT-FACETS: DR corner facet front X 1052 = 1250 - 198"
equation "dt_xr = 1699 mm" comment "SKELETON P04 SOURCE: V1-FRONT-FACETS: DT/DR joint at the top, X 449 = -1250 + 1699 (PM ruling pass C)"
equation "dr_yc = 672 mm" comment "SKELETON P04 SOURCE: V1-FRONT-FACETS: DR corner facet back Y -672"
equation "fix_xbl = door_xbr + ( door_zb - fix_zb ) * ( door_xbr - door_xtr ) / ( door_zt - door_zb ) + glass_gap * sqrt(( door_xbr - door_xtr ) * ( door_xbr - door_xtr ) + ( door_zt - door_zb ) * ( door_zt - door_zb )) / ( door_zt - door_zb )" comment "SKELETON P04 CALCULATION: F-014: fixed glass bottom-left, on the line glass_gap from the door's slanted edge (was v1's 1468)"
equation "fix_xtl = door_xbr + ( door_zb - fix_zt ) * ( door_xbr - door_xtr ) / ( door_zt - door_zb ) + glass_gap * sqrt(( door_xbr - door_xtr ) * ( door_xbr - door_xtr ) + ( door_zt - door_zb ) * ( door_zt - door_zb )) / ( door_zt - door_zb )" comment "SKELETON P04 CALCULATION: F-014: fixed glass top-left, on the same line (was v1's 1184)"
equation "floor_top = mat_t + floor_t" comment "SKELETON P04 CALCULATION: D-72: the floor top, Z 12 (mat 3 + ply 9); the threshold stands thresh_h above the room floor"
equation "wall_z0 = glide_h + band_h" comment "SKELETON P04 CALCULATION: base band top: glides + band"
equation "panel_z0 = wall_z0 + seam_gap" comment "SKELETON P04 CALCULATION: walls stand one seam_gap above the band top (joints register 2.8, IF-01)"
equation "wall_h = pod_h - wall_z0" comment "SKELETON P04 CALCULATION: 2290 = layout study v2_model wall_h"
equation "side_h = ( wall_h - 2 * seam_gap ) / 2" comment "SKELETON P04 CALCULATION: D-23: 2 sheets per side wall; the gap on the band and the horizontal seam (joints register 2.8)"
equation "side_l = wall_depth - seam_gap" comment "SKELETON P04 CALCULATION: side panel length along Y: the seam_gap at the decor's back plate (joints register 2.8, IF-07)"
equation "back_oh = pod_h - outer_t - seam_gap - panel_z0" comment "SKELETON P04 CALCULATION: PM ruling 2026-10-31 (pass D, F-004): the back outer frames run up to the ceiling frame (pod_h - outer_t), less the seam_gap under it, closing the slot at the back top edge"
equation "back_ph = ( back_oh - seam_gap ) / 2" comment "SKELETON P04 CALCULATION: D-23: 4 sheets on the back, two equal rows with one seam_gap between them (joints register 2.8); the lower back linings match the lower row, as on the side walls"
equation "half_pw = ( pod_w - 2 * outer_t - 3 * seam_gap ) / 2" comment "SKELETON P04 CALCULATION: SKIN width of each back and ceiling panel: two skins and three seam_gap seams between the side frames (F-001, joints register 2.8)"
equation "close_gap = 5.5 mm" comment "SKELETON P04 DECIDED: PM ruling 2026-10-31 (joints register, F-011/F-012): frame gap at the closing seams B1-B2, B3-B4 and C1-C2, which have no hard stop (slotted holes, thicker gasket)"
equation "half_fw = ( pod_w - 2 * outer_t - 2 * seam_gap - close_gap ) / 2" comment "SKELETON P04 CALCULATION: FRAME width of each back and ceiling panel: the skins overhang their frames by half_pw - half_fw at the closing seam (PM ruling 2026-10-31)"
equation "inner_w = pod_w - 2 * stack_t" comment "SKELETON P04 CALCULATION: inside width between the side linings"
equation "bolt_edge_inset = 220 mm" comment "SKELETON P04 DECIDED: PM ruling 2026-10-31: on every bolted edge the end bolts sit this far in from each panel end (the FRAME end, where the bolts go), the rest evenly spaced"
equation "spigot_inset = 100 mm" comment "SKELETON P04 DECIDED: PM ruling 2026-10-31: locating spigots this far in from each panel end (round hole at one end, slot at the other)"
equation "base_bolt_edge = bolt_edge_inset" comment "SKELETON P04 DECIDED: J-BASE-01 wall to band: the edge rule (kept by this name for parts already linked)"